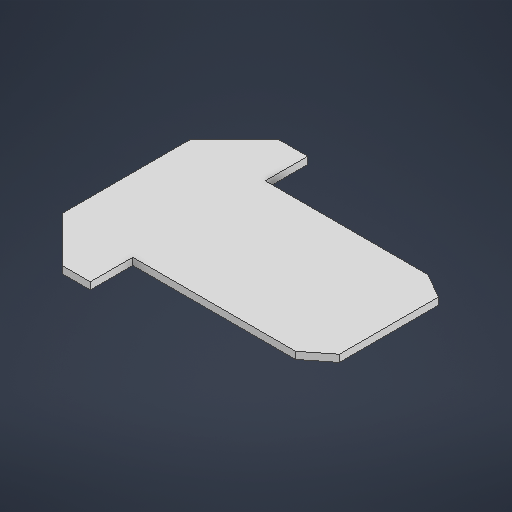
# Autodesk Inventor part: Part5
Saved by Autodesk Inventor 2026 (Build 300175000, 175)
## iProperties
Created: 2026-03-25
Part Number: Part5
Material: Generic
Document SubType Name: Modeling
Designer: PC
Density: 1 g/cm^3
Appearance: Default
Author: PC
Autodesk Inventor part; units mm, degrees
ref_plane "YZ Plane" through (0, 0, 0) normal (1, 0, 0) x (0, 1, 0)
ref_plane "XZ Plane" through (0, 0, 0) normal (0, 1, 0) x (-1, 0, 0)
ref_plane "XY Plane" through (0, 0, 0) normal (0, 0, 1) x (1, 0, 0)
sketch "Sketch5" plane through (0, 0, 0) normal (0, 1, 0) x (-1, 0, 0)
  line L0 (31.9535, 27.6117) -> (31.9535, -62.3883)
  line L1 (31.9535, -62.3883) -> (0.1337, -94.2081)
  line L2 (0.1337, -94.2081) -> (-19.8663, -94.2081)
  line L3 (-19.8663, -94.2081) -> (-19.8663, -64.2081)
  line L4 (-19.8663, -64.2081) -> (-134.8663, -64.2081)
  line L5 (-134.8663, -64.2081) -> (-152.1868, -54.2081)
  line L6 (-152.1868, -54.2081) -> (-152.1868, 15.7919)
  line L7 (-152.1868, 15.7919) -> (-132.1868, 15.7919) construction
  line L8 (31.9535, 27.6117) -> (0.1337, 59.4315)
  line L9 (31.9535, 27.6117) -> (76.9535, 27.6117) construction
  line L10 (0.1337, 59.4315) -> (-19.8663, 59.4315)
  line L11 (-19.8663, 59.4315) -> (-19.8663, 29.4315)
  line L12 (-19.8663, 29.4315) -> (-134.8663, 29.4315)
  line L13 (-134.8663, 29.4315) -> (-152.1868, 15.7919)
  point P0 (0, 0)
  dimension "d9" = 90
  dimension "d10" = 45
  dimension "d11" = 135
  dimension "d12" = 20
  dimension "d13" = 30
  dimension "d14" = 115
  dimension "d15" = 20
  dimension "d16" = 150
  dimension "d17" = 70
  dimension "d25" = 45
  dimension "d26" = 135
  dimension "d27" = 20
  dimension "d28" = 30
  dimension "d29" = 115
  constraints: 28 end point, 5 perpendicular, 3 horizontal, 1 equal length, 1 parallel, 1 vertical
  measures "d9" distance of L0.start L0.end
  measures "d10" distance of L0.end L1.end
  measures "d11" angle of L0 L1
  measures "d12" distance of L1.end L2.end
  measures "d13" distance of L2.end L3.end
  measures "d14" distance of L3.end L4.end
  measures "d15" distance of L4.end L5.end
  measures "d16" angle of L4 L5
  measures "d17" distance of L5.end L6.end
  measures "d25" distance of L0.start L8.end
  measures "d26" angle of L9 L8
  measures "d27" distance of L8.end L10.end
  measures "d28" distance of L10.end L11.end
  measures "d29" distance of L11.end L12.end
extrude "Extrusion5" add sketch "Sketch5" along normal blind 5
body "Solid2"
